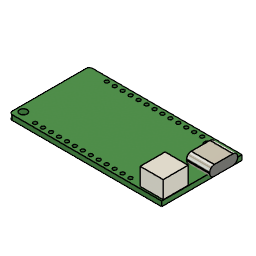
pcb-2w-robot (Autodesk Fusion 360 archive; units mm, degrees)
design "pcb-esp32-lolin32-board"
Autodesk Fusion 360 part; units mm, degrees
sketch "Sketch1" plane through (0, 0, 0) normal (0, 1, 0) x (1, 0, 0)
  line L0 (-49, 12.9) -> (0, 12.9)
  circle A0 centre (-11.4, 11.5) radius 0.6
  line L1 (-0.1, -4.3) -> (-7.5, -4.3)
  circle A1 centre (-21.6, 11.5) radius 0.6
  circle A2 centre (-29.25, 11.5) radius 0.6
  circle A3 centre (-19.05, 11.5) radius 0.6
  circle A4 centre (-13.95, 11.5) radius 0.6
  line L2 (-5.8, 0.9) -> (0, 0.9)
  circle A5 centre (-16.5, 11.5) radius 0.6
  line L3 (0, 9.9) -> (1.6, 9.9)
  circle A6 centre (-42, 11.5) radius 0.6
  circle A7 centre (-26.7, 11.5) radius 0.6
  circle A8 centre (-16.5, -11.5) radius 0.6
  circle A9 centre (-31.8, 11.5) radius 0.6
  circle A10 centre (-39.45, 11.5) radius 0.6
  line L4 (1.6, 9.9) -> (1.6, 0.9)
  circle A11 centre (-11.4, -11.5) radius 0.6
  line L5 (1.6, 0.9) -> (0, 0.9)
  circle A12 centre (-24.15, -11.5) radius 0.6
  circle A13 centre (-24.15, 11.5) radius 0.6
  line L6 (0, -12.9) -> (-49, -12.9)
  circle A14 centre (-26.7, -11.5) radius 0.6
  circle A15 centre (-29.25, -11.5) radius 0.6
  line L7 (-49, -12.9) -> (-49, 12.9)
  circle A16 centre (-31.8, -11.5) radius 0.6
  line L8 (0, 9.9) -> (-5.8, 9.9)
  line L9 (-49, 0) -> (-38.5629, 0) construction
  line L10 (0, 12.9) -> (0, -12.9)
  circle A17 centre (-13.95, -11.5) radius 0.6
  circle A18 centre (-42, -11.5) radius 0.6
  circle A19 centre (-39.45, -11.5) radius 0.6
  circle A20 centre (-34.35, 11.5) radius 0.6
  circle A21 centre (-36.9, 11.5) radius 0.6
  circle A22 centre (-36.9, -11.5) radius 0.6
  line L11 (-5.8, 9.9) -> (-5.8, 0.9)
  circle A23 centre (-34.35, -11.5) radius 0.6
  circle A24 centre (-19.05, -11.5) radius 0.6
  circle A25 centre (-21.6, -11.5) radius 0.6
  line L12 (-38.5629, 0) -> (0, 0) construction
  line L13 (-0.1, -12.3) -> (-7.5, -12.3)
  line L14 (-7.5, -12.3) -> (-7.5, -4.3)
  circle A26 centre (-8.4, 10.4) radius 1.2
  circle A27 centre (-47, -10.3) radius 1.2
  line L15 (-0.1, -4.3) -> (-0.1, -12.3)
  dimension "d3" = 30.6
  dimension "d4" = 0
  dimension "d11" = 49
  dimension "d12" = 25.8
  dimension "d13" = 9
  dimension "d14" = 1.6
  dimension "d18" = 1.2
  dimension "d19" = 7
  dimension "d20" = 1.4
  dimension "d21" = 2.55
  dimension "d22" = 5.8
  dimension "d23" = 3
  dimension "d25" = 8
  dimension "d26" = 0.6
  dimension "d29" = 2.4
  dimension "d30" = 2.4
  dimension "d33" = 1.4
  dimension "d34" = 0.8
  dimension "d37" = 1.3
  dimension "d38" = 7.2
  dimension "d45" = 0.1
  dimension "d48" = 20.7
  dimension "d49" = 38.6
  dimension "d50" = 23
  constraint horizontal L0
  constraint vertical L10
  constraint horizontal L6
  constraint vertical L7
  constraint coincident L3.start L10
  constraint perpendicular L3 L10
  constraint perpendicular L3 L4
  constraint coincident L2.end L10
  constraint perpendicular L5 L10
  constraint midpoint L9.start L7
  constraint perpendicular L7 L9
  constraint midpoint L12.end L10
  constraint symmetric A6 A18 L12
  constraint symmetric A10 A19 L12
  constraint symmetric A21 A22 L12
  constraint symmetric A20 A23 L12
  constraint symmetric A9 A16 L12
  constraint symmetric A2 A15 L12
  constraint symmetric A7 A14 L12
  constraint symmetric A12 A13 L12
  constraint symmetric A1 A25 L12
  constraint symmetric A3 A24 L12
  constraint symmetric A5 A8 L12
  constraint symmetric A4 A17 L12
  constraint symmetric A0 A11 L12
  constraint perpendicular L3 L11
  constraint collinear L2 L5
  constraint coincident L12.end origin
  constraint parallel L6 L13
  constraint horizontal L1
  constraint vertical L14
  constraint perpendicular L13 L15
  measures "d11" distance of L6.start L6.end
  measures "d12" distance of L0.end L6.start
  measures "d13" distance of L4.end L3.end
  measures "d14" distance of L4 L10
  measures "d18" diameter of A6
  measures "d19" distance of A6.centre L7
  measures "d20" distance of A6.centre L0
  measures "d21" distance of A2.centre A7.centre
  measures "d22" distance of L10 L11
  measures "d23" distance of L0 L8
  measures "d25" distance of L1 L13
  measures "d26" distance of L6 L13
  measures "d29" diameter of A26
  measures "d30" diameter of A27
  measures "d33" distance of L6 A27
  measures "d34" distance of L7 A27
  measures "d37" distance of L0 A26
  measures "d38" distance of L10 A26
  measures "d45" distance of L10 L15
  measures "d48" vertical distance of A26.centre A27.centre
  measures "d49" horizontal distance of A26.centre A27.centre
  measures "d50" distance of A18.centre A6.centre
extrude "Extrude1" add sketch "Sketch1" against normal blind 1.6 contours L0 L2 L6 L7 L8 L10 L11 | L2 L8 L10 L11 | L1 L13 L14 L15 makes body 1
extrude "Extrude2" add sketch "Sketch1" along normal blind 3.3 separate body contours L2 L8 L10 L11 | L3 L4 L5 L10 makes body 2
fillet "Fillet1" radius 1.5 4 edges at (-2.1, 3.3, -0.9) (-2.1, 0, -0.9) (-2.1, 3.3, -9.9) (-2.1, 0, -9.9) on bodies 2
extrude "Extrude3" add sketch "Sketch1" along normal blind 5.6 contours L1 L13 L14 L15 bodies 1
combine "Combine1" operation add target body 1 tool bodies 2
fillet "Fillet2" radius 1 2 edges at (-49, -0.8, 12.9) (-49, -0.8, -12.9) on bodies 1
equation "d22 = 7.4 mm - 1.6 mm"
equation "d30 = d29"
equation "d43 = 7.2 mm - 1.6 mm"
named bodies: "PCB"
